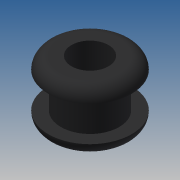
# Autodesk Inventor part: S45 ONYX STANDARD METAL GEAR SERVO (GROMMET)
Saved by Autodesk Inventor 2022.1 (Build 261234000, 234)
## iProperties
Created: 2021-08-13
Part Number: S45 ONYX STANDARD METAL GEAR SERVO (GROMMET)
Material: Rubber, Silicone
Document SubType Name: Modeling
Designer: dotwibo2
Mass: 0.0935584 g
Surface Area: 1.98628 cm^2
Volume: 0.0748467 cm^3
Density: 1.25 g/cm^3
Appearance: Rubber - Black
Author: dotwibo2
Autodesk Inventor part; units mm, degrees
ref_plane "YZ Plane" through (0, 0, 0) normal (1, 0, 0) x (0, 1, 0)
ref_plane "XZ Plane" through (0, 0, 0) normal (0, 1, 0) x (-1, 0, 0)
ref_plane "XY Plane" through (0, 0, 0) normal (0, 0, 1) x (1, 0, 0)
sketch "Sketch1" plane through (0, 0, 0) normal (0, 0, 1) x (1, 0, 0)
  line L0 (-0.7054, 0) -> (4.2323, 0) construction
  line L1 (0, -3.6077) -> (0, 3.6077) projected
  line L2 (1.475, 2.375) -> (1.475, -2.375)
  line L3 (1.475, 2.375) -> (2.35, 2.375)
  arc A0 (3.325, 1.4) -> (2.35, 2.375) centre (2.35, 1.4) ccw
  line L4 (3.325, 1.4) -> (2.325, 1.4)
  line L5 (2.325, 1.4) -> (2.325, -1.4)
  line L6 (2.325, -1.4) -> (3.325, -1.4)
  arc A1 (2.35, -2.375) -> (3.325, -1.4) centre (2.35, -1.4) ccw
  line L7 (2.35, -2.375) -> (1.475, -2.375)
  point P0 (0, 0)
  dimension "d1" = 2.95
  dimension "d2" = 4.65
  dimension "d3" = 6.65
  dimension "d4" = 4.75
  dimension "d5" = 2.8
  constraints: 12 end point, 4 horizontal, 4 point on circle, 2 centre point, 2 tangent, 2 vertical, 1 point on line, 2 other
  measures "d1" diameter of L2 L1
  measures "d2" diameter of L5 L1
  measures "d3" diameter of L4.start L1
  measures "d4" distance of L2.start L2.end
  measures "d5" distance between parallel lines of L6 L4
revolve "Revolution1" add sketch "Sketch1" angle 360 about axis through (0, -10, 0) along (0, 1, 0)
body "Solid1"
